Autodesk Fusion 360 part; units mm, degrees
(part 4 of 4)
sketch "草图16 (9)" plane through (0, 10, 0) normal (0, 1, 0) x (1, 0, 0) in component "12_front_CPU_SUPPORT_FRAME"
  circle A0 through (298.55, -132, -20) (292.4, -128.4493, -20) (292.4, -135.5507, -20)
extrude "V24 M3x6 D7 head well D8.2 compensated''" cut sketch "草图16 (9)" along normal blind 13.02 contours A0 in plane through (0, -10, 0) normal (0, 1, 0) bodies 25 in component "12_front_CPU_SUPPORT_FRAME"
ref_plane "工作平面17" through (0, 10, 0) normal (0, 1, 0) x (0, 0, 1) in component "12_front_CPU_SUPPORT_FRAME"
sketch "草图17 (6)" plane through (0, 10, 0) normal (0, 1, 0) x (1, 0, 0) in component "12_front_CPU_SUPPORT_FRAME"
  circle A0 through (298.55, -8, -20) (292.4, -4.4493, -20) (292.4, -11.5507, -20)
extrude "V24 M3x6 D7 head well D8.2 compensated (1)''" cut sketch "草图17 (6)" along normal blind 13.02 contours A0 in plane through (0, -10, 0) normal (0, 1, 0) bodies 25 in component "12_front_CPU_SUPPORT_FRAME"
ref_plane "工作平面12" through (0, 0, 143) normal (0, 0, 1) x (1, 0, 0) in component "19_PCI_LONGITUDINAL_BOARD_RAIL_243_84mm"
sketch "草图12 (12)" plane through (0, 0, 143) normal (0, 0, 1) x (1, 0, 0) in component "19_PCI_LONGITUDINAL_BOARD_RAIL_243_84mm"
  circle A0 centre (4, 225) radius 4.1
extrude "V24 M3x6 D7 head well D8.2 compensated'''" cut sketch "草图12 (12)" along normal blind 5.02 bodies 28 in component "19_PCI_LONGITUDINAL_BOARD_RAIL_243_84mm"
ref_plane "工作平面13" through (0, 0, 143) normal (0, 0, 1) x (1, 0, 0) in component "19_PCI_LONGITUDINAL_BOARD_RAIL_243_84mm"
sketch "草图13 (11)" plane through (0, 0, 143) normal (0, 0, 1) x (1, 0, 0) in component "19_PCI_LONGITUDINAL_BOARD_RAIL_243_84mm"
  circle A0 centre (4, 20) radius 4.1
extrude "V24 M3x6 D7 head well D8.2 compensated (1)'''" cut sketch "草图13 (11)" along normal blind 5.02 bodies 28 in component "19_PCI_LONGITUDINAL_BOARD_RAIL_243_84mm"
ref_plane "工作平面17" through (0, 0, 143) normal (0, 0, 1) x (1, 0, 0) in component "19_MID_LONGITUDINAL_BOARD_RAIL_243_84mm"
sketch "草图17 (7)" plane through (0, 0, 143) normal (0, 0, 1) x (1, 0, 0) in component "19_MID_LONGITUDINAL_BOARD_RAIL_243_84mm"
  circle A0 centre (134, 222.5) radius 4.1
extrude "V24 M3x6 D7 head well D8.2 compensated''''" cut sketch "草图17 (7)" along normal blind 5.02 bodies 29 in component "19_MID_LONGITUDINAL_BOARD_RAIL_243_84mm"
ref_plane "工作平面18" through (0, 0, 143) normal (0, 0, 1) x (1, 0, 0) in component "19_MID_LONGITUDINAL_BOARD_RAIL_243_84mm"
sketch "草图18 (5)" plane through (0, 0, 143) normal (0, 0, 1) x (1, 0, 0) in component "19_MID_LONGITUDINAL_BOARD_RAIL_243_84mm"
  circle A0 centre (134, 3) radius 4.1
extrude "V24 M3x6 D7 head well D8.2 compensated (1)''''" cut sketch "草图18 (5)" along normal blind 5.02 bodies 29 in component "19_MID_LONGITUDINAL_BOARD_RAIL_243_84mm"
ref_plane "工作平面12" through (0, 0, 143) normal (0, 0, 1) x (1, 0, 0) in component "19_CPU_LONGITUDINAL_BOARD_RAIL_243_84mm"
sketch "草图12 (13)" plane through (0, 0, 143) normal (0, 0, 1) x (1, 0, 0) in component "19_CPU_LONGITUDINAL_BOARD_RAIL_243_84mm"
  circle A0 centre (294, 225) radius 4.1
extrude "V24 M3x6 D7 head well D8.2 compensated'''''" cut sketch "草图12 (13)" along normal blind 5.02 bodies 30 in component "19_CPU_LONGITUDINAL_BOARD_RAIL_243_84mm"
ref_plane "工作平面13" through (0, 0, 143) normal (0, 0, 1) x (1, 0, 0) in component "19_CPU_LONGITUDINAL_BOARD_RAIL_243_84mm"
sketch "草图13 (12)" plane through (0, 0, 143) normal (0, 0, 1) x (1, 0, 0) in component "19_CPU_LONGITUDINAL_BOARD_RAIL_243_84mm"
  circle A0 centre (294, 20) radius 4.1
extrude "V24 M3x6 D7 head well D8.2 compensated (1)'''''" cut sketch "草图13 (12)" along normal blind 5.02 bodies 30 in component "19_CPU_LONGITUDINAL_BOARD_RAIL_243_84mm"
ref_plane "工作平面18" through (0, -256.84, 0) normal (0, 1, 0) x (0, 0, 1) in component "18_ONE_PIECE_REAR_LOAD_BEAM_304_45mm"
sketch "草图18 (6)" plane through (0, -256.84, 0) normal (0, 1, 0) x (1, 0, 0) in component "18_ONE_PIECE_REAR_LOAD_BEAM_304_45mm"
  circle A0 through (298.1, -132, 513.68) (291.95, -128.4493, 513.68) (291.95, -135.5507, 513.68)
extrude "V24 M3x6 D7 head well D8.2 compensated''''''" cut sketch "草图18 (6)" along normal blind 5.02 contours A0 in plane through (0, 256.84, 0) normal (0, 1, 0) bodies 31 in component "18_ONE_PIECE_REAR_LOAD_BEAM_304_45mm"
ref_plane "工作平面19" through (0, -256.84, 0) normal (0, 1, 0) x (0, 0, 1) in component "18_ONE_PIECE_REAR_LOAD_BEAM_304_45mm"
sketch "草图19 (3)" plane through (0, -256.84, 0) normal (0, 1, 0) x (1, 0, 0) in component "18_ONE_PIECE_REAR_LOAD_BEAM_304_45mm"
  circle A0 through (8.1, -132, 513.68) (1.95, -128.4493, 513.68) (1.95, -135.5507, 513.68)
extrude "V24 M3x6 D7 head well D8.2 compensated (1)''''''" cut sketch "草图19 (3)" along normal blind 5.02 contours A0 in plane through (0, 256.84, 0) normal (0, 1, 0) bodies 31 in component "18_ONE_PIECE_REAR_LOAD_BEAM_304_45mm"
ref_plane "工作平面22" through (0, 0, 143) normal (0, 0, 1) x (1, 0, 0) in component "20_ONE_PIECE_DUAL_140_FAN_RAIL_284mm"
sketch "草图22 (2)" plane through (0, 0, 143) normal (0, 0, 1) x (1, 0, 0) in component "20_ONE_PIECE_DUAL_140_FAN_RAIL_284mm"
  circle A0 centre (265, 2) radius 4.1
extrude "V24 M3x6 D7 head well D8.2 compensated'''''''" cut sketch "草图22 (2)" along normal blind 11.02 bodies 32 in component "20_ONE_PIECE_DUAL_140_FAN_RAIL_284mm"
ref_plane "工作平面23" through (0, 0, 143) normal (0, 0, 1) x (1, 0, 0) in component "20_ONE_PIECE_DUAL_140_FAN_RAIL_284mm"
sketch "草图23 (2)" plane through (0, 0, 143) normal (0, 0, 1) x (1, 0, 0) in component "20_ONE_PIECE_DUAL_140_FAN_RAIL_284mm"
  circle A0 centre (200, 2) radius 4.1
extrude "V24 M3x6 D7 head well D8.2 compensated (1)'''''''" cut sketch "草图23 (2)" along normal blind 11.02 bodies 32 in component "20_ONE_PIECE_DUAL_140_FAN_RAIL_284mm"
ref_plane "工作平面24" through (0, 0, 143) normal (0, 0, 1) x (1, 0, 0) in component "20_ONE_PIECE_DUAL_140_FAN_RAIL_284mm"
sketch "草图24 (2)" plane through (0, 0, 143) normal (0, 0, 1) x (1, 0, 0) in component "20_ONE_PIECE_DUAL_140_FAN_RAIL_284mm"
  circle A0 centre (110, 2) radius 4.1
extrude "V24 M3x6 D7 head well D8.2 compensated (2)'" cut sketch "草图24 (2)" along normal blind 11.02 bodies 32 in component "20_ONE_PIECE_DUAL_140_FAN_RAIL_284mm"
ref_plane "工作平面25" through (0, 0, 143) normal (0, 0, 1) x (1, 0, 0) in component "20_ONE_PIECE_DUAL_140_FAN_RAIL_284mm"
sketch "草图25 (2)" plane through (0, 0, 143) normal (0, 0, 1) x (1, 0, 0) in component "20_ONE_PIECE_DUAL_140_FAN_RAIL_284mm"
  circle A0 centre (50, 2) radius 4.1
extrude "V24 M3x6 D7 head well D8.2 compensated (3)'" cut sketch "草图25 (2)" along normal blind 11.02 bodies 32 in component "20_ONE_PIECE_DUAL_140_FAN_RAIL_284mm"
component "10_GPU_140_FAN_MOUNT" placed x (1, 0, 0) y (0, 1, 0) z (0, 0, 1) at (0, 0, -50)
component "10_CPU_140_FAN_MOUNT" placed x (1, 0, 0) y (0, 1, 0) z (0, 0, 1) at (0, 0, -50)
component "REF_CASE_FAN_GPU_140x140x25" placed x (1, 0, 0) y (0, 1, 0) z (0, 0, 1) at (0, 0, -50)
component "REF_AIRFLOW_GPU_FRONT_TO_REAR" placed x (1, 0, 0) y (0, 1, 0) z (0, 0, 1) at (0, 0, -50)
component "REF_CASE_FAN_CPU_140x140x25" placed x (1, 0, 0) y (0, 1, 0) z (0, 0, 1) at (0, 0, -50)
component "REF_AIRFLOW_CPU_FRONT_TO_REAR" placed x (1, 0, 0) y (0, 1, 0) z (0, 0, 1) at (0, 0, -50)
component "REF_BOARD_304.8x243.84_NUMBERED_HOLES" placed x (1, 0, 0) y (0, 1, 0) z (0, 0, 1) at (0, 0, -50)
component "REF_CPU_RIGHT" placed x (1, 0, 0) y (0, 1, 0) z (0, 0, 1) at (0, 0, -50)
component "REF_MEMORY_RIGHT_FRONT" placed x (1, 0, 0) y (0, 1, 0) z (0, 0, 1) at (0, 0, -50)
component "REF_PRIMARY_PCIE_X126.4_APPROX" placed x (1, 0, 0) y (0, 1, 0) z (0, 0, 1) at (0, 0, -50)
component "REF_SECOND_LONG_PCIE_X60_APPROX" placed x (1, 0, 0) y (0, 1, 0) z (0, 0, 1) at (0, 0, -50)
component "REF_GPU_FANS_TO_MINUS_X" placed x (1, 0, 0) y (0, 1, 0) z (0, 0, 1) at (0, 0, -50)
component "REF_GPU_FAN_MARKERS_MINUS_X" placed x (1, 0, 0) y (0, 1, 0) z (0, 0, 1) at (0, 0, -50)
component "04_front_GROUND_BAR_290mm_FLAT_PSU" placed x (1, 0, 0) y (0, 1, 0) z (0, 0, 1) at (0, 0, 0)
component "04_rear_GROUND_BAR_290mm_FLAT_PSU" placed x (1, 0, 0) y (0, 1, 0) z (0, 0, 1) at (0, 0, 0)
component "05_CENTERED_FLAT_PSU_CRADLE_OPEN_INTAKE" placed x (1, 0, 0) y (0, 1, 0) z (0, 0, 1) at (0, 0, 0)
component "REF_PSU_FLAT_CENTERED_150x140x86" placed x (1, 0, 0) y (0, 1, 0) z (0, 0, 1) at (0, 0, 0)
component "REF_PSU_INTAKE_DOWN_MINUS_Z" placed x (1, 0, 0) y (0, 1, 0) z (0, 0, 1) at (0, 0, 0)
component "REF_PSU_REAR_EXHAUST_PLUS_Y" placed x (1, 0, 0) y (0, 1, 0) z (0, 0, 1) at (0, 0, 0)
component "12_front_PCI_SUPPORT_FRAME" placed x (1, 0, 0) y (0, 1, 0) z (0, 0, 1) at (0, 0, 0)
component "12_front_CPU_SUPPORT_FRAME" placed x (1, 0, 0) y (0, 1, 0) z (0, 0, 1) at (0, 0, 0)
component "16_CPU_VERTICAL_SIDE_FLUSH_TO_BEAM" placed x (1, 0, 0) y (0, 1, 0) z (0, 0, 1) at (0, 0, 0)
component "16_PCI_INSET_SIDE_16_45mm" placed x (1, 0, 0) y (0, 1, 0) z (0, 0, 1) at (0, 0, 0)
component "19_PCI_LONGITUDINAL_BOARD_RAIL_243_84mm" placed x (1, 0, 0) y (0, 1, 0) z (0, 0, 1) at (0, 0, 0)
component "19_MID_LONGITUDINAL_BOARD_RAIL_243_84mm" placed x (1, 0, 0) y (0, 1, 0) z (0, 0, 1) at (0, 0, 0)
component "19_CPU_LONGITUDINAL_BOARD_RAIL_243_84mm" placed x (1, 0, 0) y (0, 1, 0) z (0, 0, 1) at (0, 0, 0)
component "18_ONE_PIECE_REAR_LOAD_BEAM_304_45mm" placed x (1, 0, 0) y (0, 1, 0) z (0, 0, 1) at (0, 0, 0)
component "20_ONE_PIECE_DUAL_140_FAN_RAIL_284mm" placed x (1, 0, 0) y (0, 1, 0) z (0, 0, 1) at (0, 0, 0)
component "07_GPU_INTEGRATED_LIGHTWEIGHT_FRAME" placed x (1, 0, 0) y (0, 1, 0) z (0, 0, 1) at (0, 0, 0)
equation "desk_limit = 290 mm" comment "V03 layout review; fixed profiles require regeneration"
equation "footprint_width = 290 mm" comment "V03 layout review; fixed profiles require regeneration"
equation "board_width = 304.8 mm" comment "V03 layout review; fixed profiles require regeneration"
equation "board_depth = 243.84 mm" comment "V03 layout review; fixed profiles require regeneration"
equation "board_bottom_height = 208 mm" comment "V03 layout review; fixed profiles require regeneration"
equation "approx_slot_x = 126.4 mm" comment "V03 layout review; fixed profiles require regeneration"
equation "v13_rear_overall_length = 304.45 mm" comment "V13 manufacturing reference; geometry controlled by named feature sketches"
equation "v13_fan_rail_length = 284 mm" comment "V13 manufacturing reference; geometry controlled by named feature sketches"
equation "v13_bed_side = 256 mm" comment "V13 manufacturing reference; geometry controlled by named feature sketches"
equation "v13_insert_pilot = 4.7 mm" comment "V13 manufacturing reference; geometry controlled by named feature sketches"
equation "v13_screw_clearance = 3.4 mm" comment "V13 manufacturing reference; geometry controlled by named feature sketches"
equation "v13_head_well = 6.6 mm" comment "V13 manufacturing reference; geometry controlled by named feature sketches"
equation "v14_gpu_head_channel = 8.2 mm" comment "Nominal; compensate observed 0.6 mm undersize; physical retest required"
equation "v14_gpu_ear_offset = 3 mm" comment "Upper holes and platform front extended towards minus Y"
equation "v15_platform_extension = 2 mm" comment "User revised platform only; upper insert centres unchanged"
equation "v16_ear_front_retraction = 2 mm" comment "From original V13 front; vertical thickness remains 10 mm"
equation "v16_ear_hole_rear_offset = 1.5 mm" comment "From original V13 hole centres, towards tower"
equation "v16_lower_guide_right_x = 132 mm" comment "Expose X140 base screw; preserve both GPU metal tab slots"
equation "v16_forward_foot_right_x = 150 mm" comment "First X158 base screw omitted; tower rear supports retained"
equation "v17_gpu_bracket_width = 80 mm" comment "Overall X70 to X150; aligned to V16 forward foot"
equation "v17_right_adjustment_x = 140 mm" comment "Right upper/lower clamps moved from X164 to X140"
equation "v17_display_window_width = 44 mm" comment "X88 to X132; compare physical display connector bodies"
equation "v18_tab_slot_length = 38 mm" comment "Continuous X87..125, old outer ends X89..123"
equation "v18_tab_slot_outer_extra = 2 mm" comment "Each outer end widened 2 mm"
equation "v18_tab_slot_thickness = 2.4 mm" comment "Keep V17 fore-aft clearance unchanged"
equation "v19_upper_lowest_offset = -14 mm" comment "Confirmed by user: upper screws at Z262 slot bottom"
equation "v19_upper_ledge_top = 268 mm" comment "Fixed lowest upper bearing face"
equation "v19_lower_guide_top = 158 mm" comment "Lower guide unchanged at minimum"
equation "v19_fixed_back_wall = 12 mm" comment "No adjustment holes; flat back for printing"
equation "v19_base_driver_relief = 10.6 mm" comment "Permanent access required with nonremovable ledge"
equation "v20_upper_lowest_offset = -14 mm" comment "Confirmed by user: upper screws at Z262 slot bottom"
equation "v20_upper_ledge_top = 268 mm" comment "Fixed lowest upper bearing face"
equation "v20_lower_guide_top = 158 mm" comment "Lower guide unchanged at minimum"
equation "v20_fixed_back_wall = 8 mm" comment "No adjustment holes; flat back for printing"
equation "v20_base_driver_relief = 10.6 mm" comment "Permanent access required with nonremovable ledge"
equation "v22_psu_end_clearance = 0.4 mm" comment "V22 nominal PSU end stop dimension; physical fit required"
equation "v22_psu_stop_height = 14 mm" comment "V22 nominal PSU end stop dimension; physical fit required"
equation "v22_psu_stop_thickness = 4 mm" comment "V22 nominal PSU end stop dimension; physical fit required"
equation "v23_fan_pitch = 125 mm" comment "Measured fan and short self tapping screw; print fit requires test"
equation "v23_fan_clearance_diameter = 5.5 mm" comment "Measured fan and short self tapping screw; print fit requires test"
equation "v23_fan_head_counterbore_diameter = 7 mm" comment "Measured fan and short self tapping screw; print fit requires test"
equation "v23_fan_remaining_web = 3 mm" comment "Measured fan and short self tapping screw; print fit requires test"
equation "v24_M3_D7_head_well = 8.2 mm" comment "D7 head; nominal print shrink 0.3 to 0.6; target physical clear >=7.5 mm, verify test"
